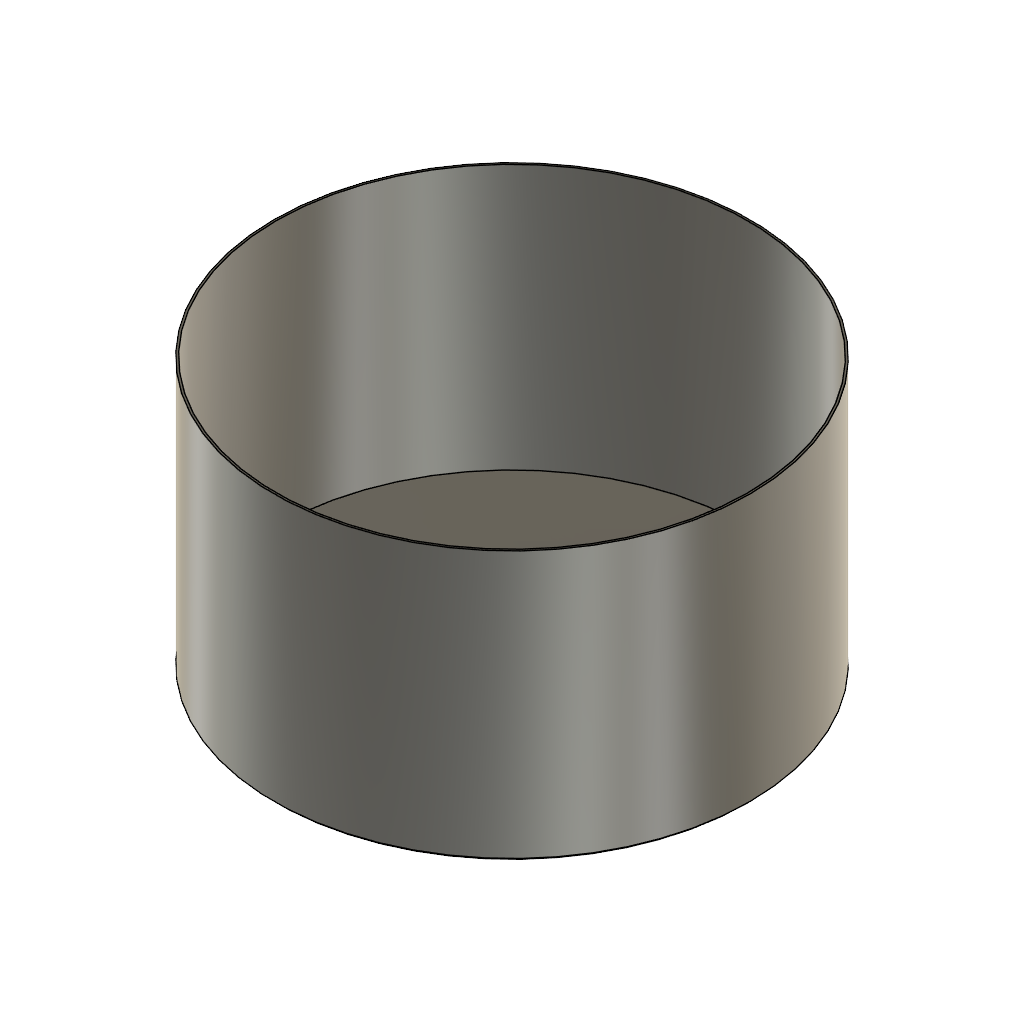
LD-S17_printed_dish_115x65 (Autodesk Fusion 360 design; units mm, degrees)
part number: 2026-11-13-16-35-24-007
part number: 2026-11-13-16-35-27-827
Autodesk Fusion 360 part; units mm, degrees
sketch "Dish half-section" plane through (0, 0, 0) normal (0, 1, 0) x (1, 0, 0) in component "LD-S17_printed_dish_115x65"
  line L0 (0, 0) -> (56.9, 0)
  line L1 (56.9, 0) -> (57.5, -0.6)
  line L2 (57.5, -0.6) -> (57.5, -65)
  line L3 (57.5, -65) -> (57, -65)
  line L4 (57, -65) -> (57, -1)
  line L5 (57, -1) -> (0, -1)
  line L6 (0, -1) -> (0, 0)
  dimension "d6" = 57.5
  dimension "d7" = 0.5
  dimension "d8" = 65
  dimension "d9" = 1
  dimension "d10" = 0.6
  dimension "d11" = 0.6
  constraint coincident L0.start L6.end
  constraint horizontal L0
  constraint horizontal L3
  constraint horizontal L5
  constraint vertical L2
  constraint vertical L4
  constraint vertical L6
  measures "d6" distance of L2 L6
  measures "d7" distance of L2 L4
  measures "d8" distance of L0 L3
  measures "d9" distance of L0 L5
  measures "d10" horizontal distance of L0.end L1.end
  measures "d11" vertical distance of L0.end L1.end
revolve "Dish revolve" add sketch "Dish half-section" angle 360 about axis through (0, 0, 1) along (0, 0, -1) in component "LD-S17_printed_dish_115x65"
component "LD-S17_printed_dish_115x65" placed x (1, 0, 0) y (0, 1, 0) z (0, 0, 1) at (0, 0, 0)
equation "dish_od = 115 mm" comment "Outside diameter; seat LD-S09 stop bore is 116.5 mm"
equation "dish_height = 65 mm" comment "Overall height = glass dish; parked cage clears the rim by 6 mm"
equation "wall_t = 0.5 mm" comment "Wall = one vase-mode line, 0.5 mm with a 0.4 mm nozzle"
equation "floor_t = 1.0 mm" comment "Floor = 5 layers x 0.2 mm, printed in any PLA"
equation "base_chamfer = 0.6 mm" comment "Outer bottom chamfer: elephant-foot relief, eases sliding into the seat"
equation "d6 = dish_od / 2"
equation "d7 = wall_t"
equation "d8 = dish_height"
equation "d9 = floor_t"
equation "d10 = base_chamfer"
equation "d11 = base_chamfer"
named bodies: "LD-S17 printed dish"
